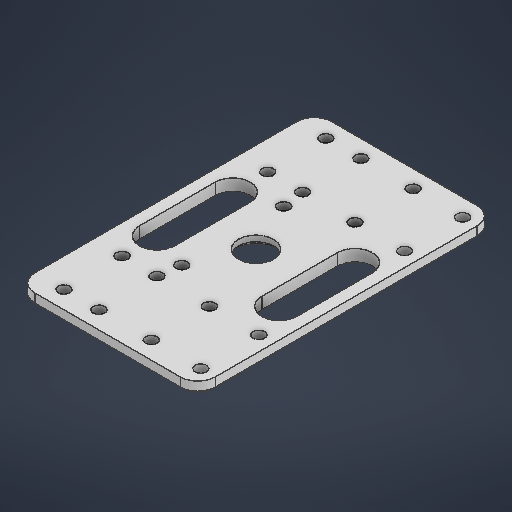
# Autodesk Inventor part: Head connection and motor stator
Saved by Autodesk Inventor 2026.2 (Build 302298010, 298A)
## iProperties
Created: 2026-05-02
Part Number: Head connection and motor stator
Material: 일반
Document SubType Name: Modeling
Designer: work
Density: 1 g/cm^3
Appearance: 기본값
Author: work
Autodesk Inventor part; units mm, degrees
ref_plane "YZ Plane" through (0, 0, 0) normal (1, 0, 0) x (0, 1, 0)
ref_plane "XZ Plane" through (0, 0, 0) normal (0, 1, 0) x (-1, 0, 0)
ref_plane "XY Plane" through (0, 0, 0) normal (0, 0, 1) x (1, 0, 0)
sketch "스케치1" plane through (0, 0, 0) normal (0, 1, 0) x (-1, 0, 0)
  line L0 (-9, 10) -> (-26, 10) construction
  line L1 (-26, 10) -> (-26, -10) construction
  line L2 (-26, -10) -> (-9, -10) construction
  line L3 (-9, -10) -> (-9, 10) construction
  line L4 (-9, 0) -> (9, 0) construction
  line L5 (21, 10) -> (9, 10) construction
  line L6 (9, 10) -> (9, -10) construction
  line L7 (9, -10) -> (21, -10) construction
  line L8 (21, -10) -> (21, 10) construction
  circle A0 centre (21, 10) radius 2
  circle A1 centre (9, 10) radius 2
  circle A2 centre (9, -10) radius 2
  circle A3 centre (21, -10) radius 2
  circle A4 centre (-9, 10) radius 2
  circle A5 centre (-9, -10) radius 2
  circle A6 centre (-26, -10) radius 2
  circle A7 centre (-26, 10) radius 2
  line L9 (-9, -60) -> (-26, -60) construction
  line L10 (-26, -60) -> (-26, -80) construction
  line L11 (-26, -80) -> (-9, -80) construction
  line L12 (-9, -80) -> (-9, -60) construction
  line L13 (-9, -70) -> (9, -70) construction
  line L14 (21, -60) -> (9, -60) construction
  line L15 (9, -60) -> (9, -80) construction
  line L16 (9, -80) -> (21, -80) construction
  line L17 (21, -80) -> (21, -60) construction
  circle A8 centre (21, -60) radius 2
  circle A9 centre (9, -60) radius 2
  circle A10 centre (9, -80) radius 2
  circle A11 centre (21, -80) radius 2
  circle A12 centre (-9, -60) radius 2
  circle A13 centre (-9, -80) radius 2
  circle A14 centre (-26, -80) radius 2
  circle A15 centre (-26, -60) radius 2
  line L18 (0, 0) -> (0, -70) construction
  circle A16 centre (0, -35) radius 6
  line L19 (0, -35) -> (8, -35) construction
  line L20 (8, -17.5) -> (8, -52.5) construction
  line L21 (8, -17.5) -> (43, -17.5) construction
  circle A17 centre (8, -17.5) radius 2
  circle A18 centre (8, -52.5) radius 2
  line L22 (-31, 16) -> (31, 16)
  line L23 (31, 16) -> (31, -86)
  line L24 (31, -86) -> (-31, -86)
  line L25 (-31, -86) -> (-31, 16)
  line L26 (-31, 16) -> (31, -86) construction
  line L27 (31, 16) -> (-31, -86) construction
  line L28 (-27, -16) -> (-15, -16)
  line L29 (-15, -16) -> (-15, -54)
  line L30 (-15, -54) -> (-27, -54)
  line L31 (-27, -54) -> (-27, -16)
  line L32 (-27, -16) -> (-15, -54) construction
  line L33 (-15, -16) -> (-27, -54) construction
  line L34 (-31, -35) -> (31, -35) construction
  line L35 (31, 16) -> (-31, -86) construction
  line L36 (-31, 16) -> (31, -86) construction
  line L37 (27, -16) -> (15, -16)
  line L38 (15, -16) -> (15, -54)
  line L39 (15, -54) -> (27, -54)
  line L40 (27, -54) -> (27, -16)
  line L41 (27, -16) -> (15, -54) construction
  line L42 (15, -16) -> (27, -54) construction
  line L43 (31, -35) -> (-31, -35) construction
  point P0 (-21, -35)
  point P1 (-17.5, -60)
  point P2 (21, -35)
  point P3 (-27, 11.7321)
  point P4 (-27, 8.2679)
  point P5 (-27, -8.2679)
  point P6 (-27, -11.7321)
  point P7 (-27, -58.2679)
  point P8 (-27, -61.7321)
  point P9 (-27, -78.2679)
  point P10 (-27, -81.7321)
  dimension "d0" = 20
  dimension "d1" = 18
  dimension "d2" = 17
  dimension "d3" = 12
  dimension "d4" = 20
  dimension "d5" = 4
  dimension "d6" = 4
  dimension "d7" = 4
  dimension "d8" = 4
  dimension "d9" = 4
  dimension "d10" = 4
  dimension "d11" = 4
  dimension "d12" = 4
  dimension "d13" = 20
  dimension "d14" = 18
  dimension "d15" = 17
  dimension "d16" = 12
  dimension "d17" = 20
  dimension "d18" = 4
  dimension "d19" = 4
  dimension "d20" = 4
  dimension "d21" = 4
  dimension "d22" = 4
  dimension "d23" = 4
  dimension "d24" = 4
  dimension "d25" = 4
  dimension "d26" = 70
  dimension "d27" = 12
  dimension "d28" = 8
  dimension "d29" = 35
  dimension "d30" = 90
  dimension "d31" = 4
  dimension "d32" = 4
  dimension "d33" = 10
  dimension "d34" = 6
  dimension "d35" = 6
  dimension "d36" = 4
  dimension "d37" = 10
  constraints: 88 end point, 20 coincident, 19 centre point, 15 midpoint, 12 parallel, 11 symmetric about line, 10 horizontal, 8 perpendicular, 2 point on line, 1 vertical
  measures "d0" distance of L2.end L0.start
  measures "d1" distance of L4.end L4.start
  measures "d2" distance of L1.end L2.end
  measures "d3" distance of L7.end L6.end
  measures "d4" distance of L6.end L5.end
  measures "d5" diameter of A0
  measures "d6" diameter of A1
  measures "d7" diameter of A2
  measures "d8" diameter of A3
  measures "d9" diameter of A4
  measures "d10" diameter of A5
  measures "d11" diameter of A6
  measures "d12" diameter of A7
  measures "d13" distance of L12.start L12.end
  measures "d14" distance of L13.end L13.start
  measures "d15" distance of L10.end L12.start
  measures "d16" distance of L16.end L15.end
  measures "d17" distance of L15.end L15.start
  measures "d18" diameter of A8
  measures "d19" diameter of A9
  measures "d20" diameter of A10
  measures "d21" diameter of A11
  measures "d22" diameter of A12
  measures "d23" diameter of A13
  measures "d24" diameter of A14
  measures "d25" diameter of A15
  measures "d26" distance of L18.start L18.end
  measures "d27" diameter of A16
  measures "d28" distance of L19.start L19.end
  measures "d29" distance of L20.start L20.end
  measures "d30" angle of L20 L21
  measures "d31" diameter of A17
  measures "d32" diameter of A18
  measures "d33" distance between parallel lines of L23 L8
  measures "d34" distance between parallel lines of L22 L5
  measures "d35" distance from line of point (-17.5, -60) L30
  measures "d36" distance between parallel lines of L25 L31
  measures "d37" distance of L34.start point (-21, -35)
extrude "돌출1" add sketch "스케치1" along normal blind 4
fillet "모깎기1" radius 6 12 edges at (31, 2, 16) (-31, 2, 16) (-31, 2, -86) (27, 2, -16) (15, 2, -16) (31, 2, -86) (-27, 2, -16) (-27, 2, -54) (-15, 2, -16) (-15, 2, -54) (15, 2, -54) (27, 2, -54)
chamfer "모따기1" distance 2 angle 45 1 edges at (6, 0, -35)
chamfer "모따기2" distance 1 angle 45 8 edges at (31, 0, -35) (29.2428, 0, -84.2428) (0, 0, -86) (-29.2428, 0, -84.2428) (-31, 0, -35) (-29.2428, 0, 14.2428) (0, 0, 16) (29.2428, 0, 14.2428)
